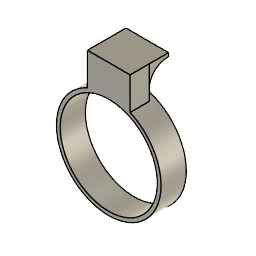
rubber band hook (Autodesk Fusion 360 design; units mm, degrees)
part number: 2025-11-06-15-43-48-877
Autodesk Fusion 360 part; units mm, degrees
sketch "Sketch1" plane through (0, 0, 0) normal (0, 1, 0) x (1, 0, 0)
  circle A0 centre (0, 0) radius 19.175
  circle A1 centre (0, 0) radius 20.675
  dimension "d1" = 38.35
  dimension "d2" = 41.35
  constraint coincident A0.centre A1.centre
  measures "d1" diameter of A0
  measures "d2" diameter of A1
extrude "Extrude1" add sketch "Sketch1" against normal blind 10
sketch "Sketch3" plane through (0, 0, 0) normal (0, 1, 0) x (1, 0, 0)
  line L0 (8.433, -20.675, -2.38) -> (8.433, -31.729, -2.38)
  line L1 (0, -20.675, -2.38) -> (8.433, -20.675, -2.38)
  line L2 (0, -20.675, -2.38) -> (-8.433, -20.675, -2.38)
  line L3 (-8.433, -18.877, -2.38) -> (-8.433, -20.675, -2.38)
  line L4 (8.433, -18.877, -2.38) -> (8.433, -20.675, -2.38)
  line L5 (8.433, -31.729, -2.38) -> (-8.433, -31.729, -2.38)
  line L6 (-8.433, -31.729, -2.38) -> (-8.433, -20.675, -2.38)
  arc A0 through (-8.433, -18.877, -2.38) (0, -20.675, -2.38) (8.433, -18.877, -2.38)
  dimension "d19" = 11.054
  dimension "d20" = 8.433
  dimension "d21" = 8.433
extrude "Extrude4" add sketch "Sketch3" against normal blind 7.62 contours L0 L1 L2 L5 L6 | L1 L4 A0 | L2 L3 A0 in plane through (0, -2.38, 0) normal (0, 1, 0)
sketch "Sketch7" plane through (-8.433, 0, 0) normal (-1, 0, 0) x (0, -1, 0)
  line L0 (2.38, 31.729) -> (2.38, 18.877)
  line L1 (2.38, 18.877) -> (10, 18.877)
  line L2 (10, 18.877) -> (10, 31.729)
  line L3 (10, 31.729) -> (2.38, 31.729)
  line L4 (2.38, 31.729) -> (-5.24, 31.729)
  line L5 (-5.24, 31.729) -> (-5.24, 30.332)
  line L6 (2.38, 31.729) -> (2.38, 23.195)
  arc A0 (2.38, 23.195) -> (-5.24, 30.332) centre (-4.7723, 23.195) ccw
  dimension "d25" = 7.62
  dimension "d26" = 1.397
  dimension "d27" = 8.534
  constraint coincident L0.start L3.end
  constraint perpendicular L0 L4
  constraint perpendicular L4 L5
  constraint perpendicular L4 L6
  constraint tangent L6 A0
  measures "d25" distance of L0.start L4.end
  measures "d26" distance of L4.end L5.end
  measures "d27" distance of L0.start L6.end
extrude "Extrude5" add sketch "Sketch7" against normal blind 16.8656 contours L0 L4 L5 L6 A0
